wall-mount (Autodesk Fusion 360 design; units mm, degrees)
Autodesk Fusion 360 part; units mm, degrees
sketch "Base" plane through (0, 0, 0) normal (0, 0, 1) x (1, 0, 0)
  circle A0 centre (0, 0) radius 34.6
  circle A1 centre (0, 0) radius 33.1
  dimension "d1" = 69.2
  constraint coincident A0.centre A1.centre
  measures "d1" diameter of A0
extrude "Extrude1" add sketch "Base" along normal blind 5 contours A1 makes body 1
extrude "Extrude2" add sketch "Base" along normal blind 12.8 bodies 1
sketch "Screws" plane through (0, 0, 5) normal (0, 0, 1) x (-1, 0, 0)
  circle A0 centre (0, 0) radius 33.1
  circle A1 centre (20, 0) radius 2
  circle A2 centre (-20, 0) radius 2
  circle A3 centre (0, 0) radius 10
  dimension "d12" = 4
  dimension "d13" = 20
  dimension "d14" = 4
  dimension "d15" = 20
  dimension "d66" = 20
  constraint coincident A0.centre A3.centre
  constraint horizontal A0.centre A1.centre
  constraint horizontal A0.centre A2.centre
  measures "d12" diameter of A1
  measures "d13" distance of A0.centre A1.centre
  measures "d14" diameter of A2
  measures "d15" distance of A0.centre A2.centre
  measures "d66" diameter of A3
sketch "Base recess" plane through (0, 0, 5) normal (0, 0, 1) x (-1, 0, 0)
  circle A0 centre (0, 0) radius 33.1
  circle A1 centre (0, 0) radius 31.3
  dimension "d19" = -1.8
extrude "Extrude4" cut sketch "Base recess" against normal blind 1 contours A1 bodies 1
sketch "Ring Cutouts" plane through (0, 0, 12.8) normal (0, 0, 1) x (-1, 0, 0)
  circle A0 centre (0, 0) radius 33.1
  circle A1 centre (0, 0) radius 34.6
  line L0 (0, 0) -> (34, 0) construction
  line L1 (0, 0) -> (34, 0) construction
  line L2 (0, 0) -> (-24.0343, 24.0343) construction
  line L3 (0, 0) -> (34, 0) construction
  line L4 (0, 0) -> (-30.8145, 14.369) construction
  line L5 (0, 0) -> (34, 0) construction
  line L6 (0, 0) -> (8.9551, 33.421) construction
  line L7 (0, 0) -> (34.5, 0) construction
  line L8 (0, 0) -> (-8.9551, 33.421) construction
  line L9 (0, 0) -> (34.5, 0) construction
  line L10 (8.5669, 31.9721) -> (8.9551, 33.421)
  line L11 (-8.5669, 31.9721) -> (-8.9551, 33.421)
  dimension "d34" = 135
  dimension "d35" = 155
  dimension "d49" = 75
  dimension "d50" = 105
  constraint horizontal L0
  constraint coincident A0.centre A1.centre
  constraint horizontal L1
  constraint horizontal L3
  constraint horizontal L5
  constraint horizontal L7
  constraint horizontal L9
  constraint coincident L6 L10.start
  constraint coincident A0 L10.start
  constraint coincident L8 L11.start
  constraint coincident A0 L11.start
  constraint coincident A1 L6.end
  constraint coincident A1 L8.end
  measures "d34" angle of L2 L3
  measures "d35" angle of L4 L5
  measures "d49" angle of L6 L7
  measures "d50" angle of L8 L9
ref_plane "WorkPlane2" through (28.3427, -19.8457, 3.0755) normal (0.819152, -0.573576, 0) x (-0.573576, -0.819152, 0)
extrude "Extrude6" cut sketch "Ring Cutouts" against normal blind 7.8 contours A0 A1 L10 L11 picked at (5.9306, 33.514) bodies 1
sketch "Side Port" plane through (28.3427, -19.8457, 0) normal (0.819152, -0.573576, 0) x (-0.573576, -0.819152, 0)
  line L0 (-5, -10.4) -> (5, -10.4)
  line L1 (5, -10.4) -> (5, -5.6)
  line L2 (5, -5.6) -> (-5, -5.6)
  line L3 (-5, -5.6) -> (-5, -10.4)
  dimension "d56" = 10
  dimension "d57" = 4.8
  dimension "d58" = 5
  dimension "d59" = 10.4
  constraint horizontal L0
  constraint vertical L1
  constraint horizontal L2
  constraint vertical L3
  measures "d56" horizontal distance of L0.start L0.end
  measures "d57" vertical distance of L0.start L2.end
  measures "d58" horizontal distance of origin L0.start
  measures "d59" vertical distance of origin L0.start
extrude "Side Port Cut" cut sketch "Side Port" against normal blind 6.5 bodies 1
extrude "Extrude9" cut sketch "Screws" against normal blind 5 contours A3 bodies 1
fillet "Fillet4" radius 1 6 edges at (-8.761, -32.6966, 5) (8.761, -32.6966, 5) (30.2919, -15.1067, 5.6) (24.5561, -23.2982, 5.6) (24.5561, -23.2982, 10.4) (30.2919, -15.1067, 10.4) on bodies 1
sketch "Locating Groove" plane through (0, 0, 0) normal (0, 0, 1) x (1, 0, 0)
  circle A0 centre (0, 0) radius 32.6
  circle A1 centre (0, 0) radius 30.8
  dimension "d132" = 65.2
  dimension "d133" = 61.6
  constraint coincident A0.centre A1.centre
  measures "d132" diameter of A0
  measures "d133" diameter of A1
extrude "Locating Groove (1)" cut sketch "Locating Groove" along normal blind 1.35 bodies 1
ref_plane "WorkPlane6" through (12.125, 0, 0) normal (0, 0.34202, 0.939693) x (1, 0, 0)
ref_plane "WorkPlane7" through (12.125, -5.0116, -13.7693) normal (0, 0.34202, 0.939693) x (1, 0, 0)
sketch "Wedge Disc" plane through (0, 0, 0) normal (0, 0, 1) x (1, 0, 0)
  circle A0 centre (0, 0) radius 34.6
  dimension "d165" = 69.2
  constraint coincident A0.centre origin
  measures "d165" diameter of A0
extrude "Wedge Blank" add sketch "Wedge Disc" along normal up to surface separate body end surface through (12.125, -5.0116, -13.7693) normal (0, 0.34202, 0.939693) offset 0 makes body 2
sketch "Wedge Hollow" plane through (0, 0, 0) normal (0, 0, 1) x (1, 0, 0)
  circle A0 centre (0, 0) radius 27.6
  dimension "d168" = 55.2
  constraint coincident A0.centre origin
  measures "d168" diameter of A0
sketch "Locating Ring" plane through (0, 0, 0) normal (0, 0, 1) x (1, 0, 0)
  circle A0 centre (0, 0) radius 32.45
  circle A1 centre (0, 0) radius 30.95
  dimension "d187" = 64.9
  dimension "d188" = 61.9
  constraint coincident A0.centre A1.centre
  measures "d187" diameter of A0
  measures "d188" diameter of A1
extrude "Locating Ring (1)" add sketch "Locating Ring" along normal blind 1.2 and the other way blind 0.5 bodies 2
extrude "Wedge Hollow (1)" cut sketch "Wedge Hollow" against normal blind 33.1867 from surface at -6 bodies 2
sketch "Mount Slots" plane through (0, 0, 0) normal (1, 0, 0) x (0, 0, -1)
  line L0 (1, 23.75) -> (-5, 23.75)
  line L1 (-5, 23.75) -> (-5, 27.25)
  line L2 (-5, 27.25) -> (1, 27.25)
  line L3 (1, 27.25) -> (1, 23.75)
  line L4 (1, -23.75) -> (-5, -23.75)
  line L5 (-5, -23.75) -> (-5, -27.25)
  line L6 (-5, -27.25) -> (1, -27.25)
  line L7 (1, -27.25) -> (1, -23.75)
  dimension "d266" = 23.75
  dimension "d267" = 27.25
  dimension "d268" = 1
  dimension "d269" = 5
  dimension "d270" = 23.75
  dimension "d271" = 27.25
  dimension "d272" = 1
  dimension "d273" = 5
  constraint horizontal L0
  constraint vertical L1
  constraint horizontal L2
  constraint vertical L3
  constraint horizontal L4
  constraint vertical L5
  constraint horizontal L6
  constraint vertical L7
  measures "d266" vertical distance of origin L0.start
  measures "d267" vertical distance of origin L1.end
  measures "d268" horizontal distance of origin L0.start
  measures "d269" horizontal distance of origin L0.end
  measures "d270" vertical distance of origin L4.start
  measures "d271" vertical distance of origin L5.end
  measures "d272" horizontal distance of origin L4.start
  measures "d273" horizontal distance of origin L4.end
revolve "Mount Slots (1)" cut sketch "Mount Slots" angle 75 about axis through (0, 0, 1.75) along (0, 0, 1) second angle 75 bodies 1
sketch "Wedge Deck Hole" plane through (0, 0, 0) normal (0, 0, 1) x (1, 0, 0)
  circle A0 centre (0, 0) radius 15
  dimension "d286" = 30
  constraint coincident A0.centre origin
  measures "d286" diameter of A0
extrude "Wedge Deck Hole (1)" cut sketch "Wedge Deck Hole" against normal blind 33.1867 bodies 2
sketch "Wedge Slots" plane through (0, 0, 0) normal (1, 0, 0) x (0, 0, -1)
  line L0 (7, 24.5) -> (-1, 24.5)
  line L1 (-1, 24.5) -> (-1, 26.5)
  line L2 (-1, 26.5) -> (7, 26.5)
  line L3 (7, 26.5) -> (7, 24.5)
  line L4 (7, -24.5) -> (-1, -24.5)
  line L5 (-1, -24.5) -> (-1, -26.5)
  line L6 (-1, -26.5) -> (7, -26.5)
  line L7 (7, -26.5) -> (7, -24.5)
  dimension "d289" = 24.5
  dimension "d290" = 26.5
  dimension "d291" = 7
  dimension "d292" = 1
  dimension "d293" = 24.5
  dimension "d294" = 26.5
  dimension "d295" = 7
  dimension "d296" = 1
  constraint horizontal L0
  constraint vertical L1
  constraint horizontal L2
  constraint vertical L3
  constraint horizontal L4
  constraint vertical L5
  constraint horizontal L6
  constraint vertical L7
  measures "d289" vertical distance of origin L0.start
  measures "d290" vertical distance of origin L1.end
  measures "d291" horizontal distance of origin L0.start
  measures "d292" horizontal distance of origin L1.end
  measures "d293" vertical distance of origin L4.start
  measures "d294" vertical distance of origin L5.end
  measures "d295" horizontal distance of origin L4.start
  measures "d296" horizontal distance of origin L5.end
revolve "Wedge Slots (1)" cut sketch "Wedge Slots" angle 75 about axis through (0, 0, 1.75) along (0, 0, 1) second angle 75 bodies 2
ref_plane "WorkPlane8" through (12.125, -1.0261, -2.8191) normal (0, 0.34202, 0.939693) x (1, 0, 0)
sketch "Wall Screw Bosses" plane through (0, -1.0261, -2.8191) normal (0, 0.34202, 0.939693) x (1, 0, 0)
  circle A0 centre (23, 0) radius 6
  circle A1 centre (-23, 0) radius 6
  dimension "d311" = 23
  dimension "d312" = 12
  dimension "d313" = 23
  dimension "d314" = 12
  constraint horizontal origin A0.centre
  constraint horizontal origin A1.centre
  measures "d311" horizontal distance of origin A0.centre
  measures "d312" diameter of A0
  measures "d313" horizontal distance of origin A1.centre
  measures "d314" diameter of A1
extrude "Wall Screw Bosses (1)" add sketch "Wall Screw Bosses" against normal up to surface (11.653 mm away) bodies 2
sketch "Wall Screw Holes" plane through (0, 0, 0) normal (0, 0.34202, 0.939693) x (1, 0, 0)
  circle A0 centre (23, 0) radius 2.25
  circle A1 centre (-23, 0) radius 2.25
  dimension "d317" = 23
  dimension "d318" = 4.5
  dimension "d319" = 23
  dimension "d320" = 4.5
  constraint horizontal origin A0.centre
  constraint horizontal origin A1.centre
  measures "d317" horizontal distance of origin A0.centre
  measures "d318" diameter of A0
  measures "d319" horizontal distance of origin A1.centre
  measures "d320" diameter of A1
extrude "Wall Screw Holes (1)" cut sketch "Wall Screw Holes" against normal blind 38.1867 bodies 2
ref_plane "WorkPlane9" through (12.125, 0.684, 1.8794) normal (0, 0.34202, 0.939693) x (1, 0, 0)
sketch "Wall Screw Bores" plane through (0, 0.684, 1.8794) normal (0, 0.34202, 0.939693) x (1, 0, 0)
  circle A0 centre (23, 0) radius 4
  circle A1 centre (-23, 0) radius 4
  dimension "d339" = 23
  dimension "d340" = 8
  dimension "d341" = 23
  dimension "d342" = 8
  constraint horizontal origin A0.centre
  constraint horizontal origin A1.centre
  measures "d339" horizontal distance of origin A0.centre
  measures "d340" diameter of A0
  measures "d341" horizontal distance of origin A1.centre
  measures "d342" diameter of A1
extrude "Wall Screw Bores (1)" cut sketch "Wall Screw Bores" against normal blind 5 bodies 2
ref_plane "WorkPlane10" through (12.125, -1.0261, -2.8191) normal (0, 0.34202, 0.939693) x (1, 0, 0)
sketch "Wall Screw Head Chamfers" plane through (0, -1.0261, -2.8191) normal (0, 0.34202, 0.939693) x (1, 0, 0)
  circle A0 centre (23, 0) radius 4
  circle A1 centre (-23, 0) radius 4
  dimension "d353" = 23
  dimension "d354" = 8
  dimension "d355" = 23
  dimension "d356" = 8
  constraint horizontal origin A0.centre
  constraint horizontal origin A1.centre
  measures "d353" horizontal distance of origin A0.centre
  measures "d354" diameter of A0
  measures "d355" horizontal distance of origin A1.centre
  measures "d356" diameter of A1
extrude "Wall Screw Head Chamfers (1)" cut sketch "Wall Screw Head Chamfers" against normal blind 1.75 draft -45 bodies 2
fillet "Mount Slot Ends" radius 1.75 8 edges at (22.9407, -6.147, 2) (26.3215, -7.0528, 2) (-26.3215, -7.0528, 2) (-22.9407, -6.147, 2) (-22.9407, 6.147, 2) (-26.3215, 7.0528, 2) (26.3215, 7.0528, 2) (22.9407, 6.147, 2) on bodies 1
chamfer "Mount Slot Chamfer" distance 1.5 angle 45 8 edges at (24.688, 6.6194, 4) (0, 27.25, 4) (-24.688, 6.6194, 4) (0, 23.75, 4) (-24.688, -6.6194, 4) (0, -27.25, 4) (24.688, -6.6194, 4) (0, -23.75, 4) tangent chain off on bodies 1
fillet "Wedge Slot Ends" radius 1 8 edges at (23.6652, -6.3411, -0.4423) (-23.6652, -6.3411, -0.4423) (25.597, -6.8587, -1.5149) (-25.597, -6.8587, -1.5149) (-25.597, 6.8587, -3) (-23.6652, 6.3411, -3) (23.6652, 6.3411, -3) (25.597, 6.8587, -3) on bodies 2
equation "d1 = base_dia"
equation "base_dia = dial_dia + ( wall_thickness * 2 )"
equation "wall_thickness = 1.5 mm"
equation "d4 = -wall_thickness"
equation "base_thickness = 5 mm"
equation "d6 = base_thickness"
equation "wall_height = Ring_height + base_thickness"
equation "Ring_height = 7.8 mm"
equation "d10 = wall_height"
equation "d12 = screw_dia"
equation "d13 = screw_offset"
equation "d14 = screw_dia"
equation "d15 = screw_offset"
equation "d40 = -Ring_height"
equation "dial_dia = 66.2 mm"
equation "screw_dia = 4 mm"
equation "port_width = 10 mm" comment "Side port opening width"
equation "port_height = min(port_height_max; Ring_height - port_from_top)" comment "Side port height, trimmed so it never cuts into the base ledge"
equation "port_from_top = 2.4 mm" comment "Top of side port below top of wall"
equation "d56 = port_width"
equation "d57 = port_height"
equation "d58 = port_width / 2"
equation "d59 = wall_height - port_from_top"
equation "port_height_max = 4.8 mm" comment "Wanted side port opening height"
equation "d67 = -base_thickness"
equation "d69 = -( wall_thickness + 5 mm )"
equation "wedge_angle = 20 deg" comment "Tilt of the wall wedge"
equation "wedge_min_thickness = 3 mm" comment "Thickness of the wedge at its thin edge"
equation "wedge_rise = base_dia * tan(wedge_angle)" comment "Height gained across the wedge"
equation "wedge_max_thickness = wedge_min_thickness + wedge_rise" comment "Thickness at the thick edge"
equation "screw_offset = 20 mm" comment "Screw centres from the middle, shared by bracket and wedge"
equation "wedge_wall = 7 mm" comment "Wedge rim thickness, measured in plan"
equation "wedge_boss_wall = 3 mm" comment "Material around the wedge screw holes"
equation "ring_inset = ring_lip + ring_clearance" comment "Derived: whatever puts the groove edge ring_lip in from the rim"
equation "ring_width = 1.5 mm" comment "Width of the locating ring"
equation "ring_height = 1.2 mm" comment "How far the locating ring stands proud"
equation "ring_clearance = 0.15 mm" comment "Slack between ring and groove"
equation "d132 = base_dia - 2 * ring_inset + 2 * ring_clearance"
equation "d133 = base_dia - 2 * ring_inset - 2 * ring_width - 2 * ring_clearance"
equation "d134 = ring_height + ring_clearance"
equation "wedge_fillet = 3 mm" comment "Rounding on the wedge screw blocks"
equation "ring_lip = 2 mm" comment "Material left outboard of the groove on the Wall Mount"
equation "d161 = -wedge_angle"
equation "d163 = -( wedge_min_thickness + base_dia / 2 * tan(wedge_angle) ) * cos(wedge_angle)"
equation "d165 = base_dia"
equation "d168 = base_dia - 2 * wedge_wall"
equation "d187 = base_dia - 2 * ring_inset"
equation "d188 = base_dia - 2 * ring_inset - 2 * ring_width"
equation "d189 = ring_height"
equation "wedge_deck = 6 mm" comment "Solid deck under the mating face: what the mount screws bite into"
equation "slot_radius = 25.5 mm" comment "Radius of the curved slots and the wall screws"
equation "slot_clear = 0.5 mm" comment "Slot width over screw diameter"
equation "slot_width = mount_screw_dia + 0.5 mm" comment "Width of the curved slot"
equation "head_dia = 8 mm" comment "Counterbore for a flat-seating screw head"
equation "head_seat = 1.6 mm" comment "Material left under the screw head"
equation "slot_arc = 150 deg" comment "Arc each slot sweeps; the rest is bridge"
equation "wall_boss_dia = 12 mm" comment "Tube carrying each wall screw down to the wall"
equation "d203 = -wedge_deck"
equation "d204 = -( wedge_max_thickness + 5 mm )"
equation "wall_head_depth = 5.5 mm" comment "How far the wall screw head sits below the mating face"
equation "deck_hole = 30 mm" comment "Central cutout through the wedge deck"
equation "nut_width = 7.4 mm" comment "Captive nut channel width under the wedge slot"
equation "nut_depth = 3.4 mm" comment "Depth of the nut channel, measured up from the deck underside"
equation "d266 = slot_radius - slot_width / 2"
equation "d267 = slot_radius + slot_width / 2"
equation "d269 = base_thickness"
equation "d270 = slot_radius - slot_width / 2"
equation "d271 = slot_radius + slot_width / 2"
equation "d273 = base_thickness"
equation "d274 = slot_arc / 2"
equation "d275 = slot_arc / 2"
equation "d286 = deck_hole"
equation "d287 = -( wedge_max_thickness + 5 mm )"
equation "d289 = slot_radius - pilot_width / 2"
equation "d290 = slot_radius + pilot_width / 2"
equation "d291 = wedge_deck + 1 mm"
equation "d293 = slot_radius - pilot_width / 2"
equation "d294 = slot_radius + pilot_width / 2"
equation "d295 = wedge_deck + 1 mm"
equation "d297 = slot_arc / 2"
equation "d298 = slot_arc / 2"
equation "d311 = wall_screw_radius"
equation "d312 = wall_boss_dia"
equation "d313 = wall_screw_radius"
equation "d314 = wall_boss_dia"
equation "d317 = wall_screw_radius"
equation "d318 = wall_hole_dia"
equation "d319 = wall_screw_radius"
equation "d320 = wall_hole_dia"
equation "d321 = -( wedge_max_thickness + 10 mm )"
equation "pilot_width = 2 mm" comment "Pilot slot in the wedge the mount screw threads into"
equation "mount_screw_dia = 3 mm" comment "Wood screw holding the mount to the wedge"
equation "wall_hole_dia = 4.5 mm" comment "Clearance for the wall screw shank"
equation "csk_dia = 8 mm" comment "Countersink mouth for the wall screw head"
equation "csk_rise = 2 mm" comment "How far the countersink is carried above the mating face"
equation "csk_angle = 45 deg" comment "Half angle of the countersink cone"
equation "head_chamfer = 1.5 mm" comment "Chamfer on the mount slot for the screw head"
equation "wall_screw_radius = 23 mm" comment "Radius of the two wall screws, inboard of the locating ring"
equation "d337 = csk_rise"
equation "d339 = wall_screw_radius"
equation "d340 = head_dia"
equation "d341 = wall_screw_radius"
equation "d342 = head_dia"
equation "head_sink = 3 mm" comment "Depth of the straight bore above the wall screw head chamfer"
equation "d349 = -( csk_rise + head_sink )"
equation "d351 = -head_sink"
equation "d353 = wall_screw_radius"
equation "d354 = head_dia"
equation "d355 = wall_screw_radius"
equation "d356 = head_dia"
equation "d357 = -( ( head_dia - wall_hole_dia ) / 2 / tan(csk_angle) )"
equation "d358 = -csk_angle"
equation "d360 = slot_width / 2"
equation "d361 = head_chamfer"
equation "d363 = pilot_width / 2"
named bodies: "Wall Mount", "Wall Wedge"
